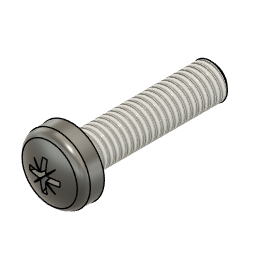
FCW v38 (Autodesk Fusion 360 archive; units mm, degrees)
design "Pan Head Screw SFS-EN ISO 7045 - M3 x 12 - Z Steel 4.6 Plain"
description: Pan Head Screw SFS-EN ISO 7045 - M3 x 12 - Z
part number: SFS-EN ISO 7045 - M3 x 12 - Z Steel 4.6 Plain
Autodesk Fusion 360 part; units mm, degrees
sketch "Sketch1" plane through (0, 0, 0) normal (0, 1, 0) x (1, 0, 0)
  line L0 (-1.5, 1) -> (-1.5, 12)
  line L1 (-1.5, 12) -> (0, 12)
  line L2 (0, 12) -> (0, -2.4)
  line L3 (-1.3647, 0) -> (-2.8, 0)
  arc A0 (-2.7449, -1.5792) -> (0, -2.4) centre (0, 2.6) ccw
  line L4 (-1.5, 1) -> (-1.3647, 0.7098)
  line L5 (-1.3647, 0.7098) -> (-1.3647, 0)
  line L6 (-2.8, 0) -> (-2.7449, -1.5792)
  dimension "d9" = 3
  dimension "d74" = 12
  dimension "d75" = 5.6
  dimension "d78" = 2.4
  dimension "d98" = 2.7294
  dimension "d102" = 1
  dimension "d103" = 155
  dimension "d137" = 2
  dimension "d139" = 5
  constraint vertical L0
  constraint perpendicular L0 L1
  constraint coincident origin L3
  constraint coincident L2 A0.centre
  constraint vertical L2
  constraint vertical L5
  constraint coincident L3.start L5.end
  constraint coincident origin L2
  constraint perpendicular L3 L5
  constraint coincident A0.start L6.end
  measures "d74" distance of origin L1.end
  measures "d78" vertical distance of L2.end L3.end
  measures "d102" distance of L3 L0.start
  measures "d103" angle of L4 L5
  measures "d137" angle of L2 L6
  measures "d139" distance of L2.end A0.centre
revolve "Revolve1" add sketch "Sketch1" angle 360 about axis through (0, 0, -12) along (0, 0, 1) makes body 1
ref_plane "WorkPlane1" through (0, 0, 2.4) normal (0, 0, 1) x (1, 0, 0)
sketch "Sketch7" plane through (0, 0, 2.4) normal (0, 0, 1) x (1, 0, 0)
  line L0 (-0.258, 0.258) -> (0.258, 0.258)
  line L1 (0.258, 0.258) -> (0.258, -0.258)
  line L2 (0.258, -0.258) -> (-0.258, -0.258)
  line L3 (-0.258, -0.258) -> (-0.258, 0.258)
  point P0 (0, 0.258)
  point P1 (-0.258, 0)
  dimension "d65" = 0.516
  dimension "d138" = 0.516
  constraint horizontal L0
  constraint perpendicular L0 L1
  constraint parallel L0 L2
  constraint parallel L1 L3
  constraint midpoint L0 P0
  constraint vertical origin P0
  constraint midpoint L3 P1
  constraint horizontal origin P1
  measures "d65" distance of L0.start L0.end
  measures "d138" distance of L0 L2
extrude "Extrude4" add sketch "Sketch7" against normal blind 1.75 draft -10 separate body makes body 2
sketch "Sketch10" plane through (0, 0, 2.4) normal (0, 0, 1) x (1, 0, 0)
  line L0 (-1.4, 0) -> (1.4, 0) construction
  line L1 (-1.4, 0.215) -> (1.4, 0.215)
  line L2 (1.4, 0.215) -> (1.4, -0.215)
  line L3 (1.4, -0.215) -> (-1.4, -0.215)
  line L4 (-1.4, -0.215) -> (-1.4, 0.215)
  line L5 (-0.215, 1.4) -> (0.215, 1.4)
  line L6 (-0.215, -1.4) -> (-0.215, 1.4)
  line L7 (0.215, 1.4) -> (0.215, -1.4)
  line L8 (0.215, -1.4) -> (-0.215, -1.4)
  dimension "d90" = 2.8
  dimension "d91" = 0.43
  dimension "d119" = 90
  constraint horizontal L0
  constraint midpoint origin L0
  constraint horizontal L1
  constraint vertical L2
  constraint horizontal L3
  constraint vertical L4
  constraint midpoint L0.start L4
  constraint midpoint L0.end L2
  measures "d90" distance of L0.start L0.end
  measures "d91" distance of L1.start L3.end
extrude "Extrude1" add sketch "Sketch10" against normal blind 1.75 draft -6 separate body makes body 3
draft "Draft2" angle -30 neutral plane through (0, 0, 2.4) pull (0, 0, 1) 4 faces at (-0.0104, 1.3387, 1.8167) (1.3387, 0.0104, 1.8167) (-1.3387, -0.0104, 1.8167) (0.0104, -1.3387, 1.8167) on bodies 3
combine "Combine1" operation cut target body 1 tool bodies 2 3
ref_plane "WorkPlane2" through (-0.1972, 1.2767, 2.2302) normal (0, 0, -1) x (-1, 0, 0)
sketch "Sketch8" plane through (-0.2873, 1.3933, 2.2302) normal (0, 0, -1) x (1, 0, 0)
  line L0 (0.2873, 1.3933) -> (1.3763, 2.4823)
  line L1 (2.0373, 1.3933) -> (22.7873, 1.3933)
  point P0 (0.2873, 1.3933)
  dimension "d83" = 1.54
  dimension "d117" = 45
  constraint coincident P0 L0.start
  measures "d83" distance of P0 L0.end
  measures "d117" angle of L0 L1
ref_plane "WorkPlane3" through (0.5445, -0.5445, 2.2302) normal (-0.664463, -0.664463, 0.34202) x (0.707107, -0.707107, 0)
sketch "Sketch9" plane through (0.6151, -0.5905, 2.278) normal (-0.664463, -0.664463, 0.34202) x (0.707107, -0.707107, 0)
  line L0 (-0.8525, -0.0508) -> (0.6875, -0.0508)
  line L1 (0.6875, -0.0508) -> (0.6875, 0.8092)
  line L2 (0.6875, 0.8092) -> (-0.8525, 0.8092)
  line L3 (-0.8525, 0.8092) -> (-0.8525, -0.0508)
  point P0 (-0.8525, -0.0508)
  point P1 (0.6875, -0.0508)
  dimension "d85" = 0.86
  constraint horizontal L0
  constraint vertical L1
  constraint horizontal L2
  constraint vertical L3
  constraint coincident P0 L0.start
  constraint coincident P1 L1
  measures "d85" distance of P1 L1.end
extrude "Extrude6" cut sketch "Sketch9" along normal blind 0.215 draft -50 bodies 1
pattern_circular "C-Pattern1" count 4 over 360 about axis through (0, 0, 1.75) along (0, 0, 1) of "Extrude6"
fillet "Fillet4" radius 0.8 1 edges at (-2.5591, 0.9926, 1.5792) on bodies 1
thread "Thread1" "ISO Metric profile 3.0 M3x0.5 6g" major diameter 2.927 minor diameter 2.3555 pitch 0.5 angle 60 resizes the face on face at (-1.4981, 0.0748, -4.6667) on bodies 1
fillet "Fillet5" radius 0.3 1 edges at (-1.2723, 0.4935, 0) on bodies 1
sketch "Sketch5" plane through (0, 0, 0) normal (0, 1, 0) x (1, 0, 0)
  line L0 (-1.53, 12) -> (-1.53, 11.6933)
  line L1 (-1.53, 11.6933) -> (-1.1933, 12)
  line L2 (0, 12) -> (0, -2.4)
  line L3 (-1.53, 12) -> (0, 12)
  dimension "d114" = 1.53
  dimension "d115" = 0.3067
  dimension "d116" = 1.1933
  constraint coincident L2.start L3.end
  constraint perpendicular L2 L3
  constraint coincident L1.end L3
  constraint perpendicular L0 L3
  measures "d114" distance of origin L0
  measures "d115" vertical distance of L0.end L1.end
  measures "d116" horizontal distance of origin L1.end
revolve "Revolve2" cut sketch "Sketch5" angle 360 about axis through (0, 0, -12) along (0, 0, 1) bodies 1
equation "d9 = adsk_nomdia"
equation "adsk_nomlen = 12.00 mm"
equation "adsk_headh = 2.40 mm"
equation "adsk_headdia = 5.60 mm"
equation "adsk_nomdia = 3.00 mm"
equation "adsk_phildia = 2.80 mm"
equation "d31 = -adsk_phildepth"
equation "adsk_philwidth = 0.43 mm"
equation "adsk_phildepth = 1.75 mm"
equation "d65 = adsk_philwidth * 1.2"
equation "d68 = -adsk_phildepth"
equation "d74 = adsk_nomlen"
equation "d75 = adsk_headdia"
equation "d78 = adsk_headh"
equation "d79 = adsk_headh"
equation "d83 = adsk_phildia / 2 * 1.1"
equation "d85 = adsk_philwidth * 2"
equation "d86 = adsk_philwidth / 2"
equation "d90 = adsk_phildia"
equation "d91 = adsk_philwidth"
equation "adsk_thrlen = 11.00 mm"
equation "d98 = adsk_shnkdia"
equation "adsk_shnkdia = 2.72937 mm"
equation "d102 = adsk_nomlen - adsk_thrlen"
equation "adsk_endpointdia = 2.38655 mm"
equation "adsk_startlen = 0.306725 mm"
equation "d114 = adsk_nomdia * 0.51"
equation "d115 = adsk_startlen"
equation "d116 = adsk_endpointdia / 2"
equation "adsk_ovalrad = 5.00 mm"
equation "adsk_headang = 2.00 deg"
equation "adsk_headtoprad = adsk_headh / 3"
equation "d132 = adsk_midfillet"
equation "adsk_midfillet = adsk_nomdia * 0.1"
equation "d136 = adsk_headtoprad"
equation "d137 = adsk_headang"
equation "d138 = adsk_philwidth * 1.2"
equation "d139 = adsk_ovalrad"

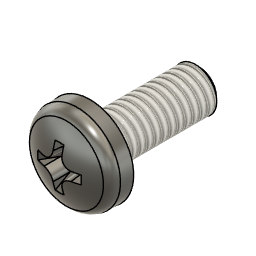
design "Pan Head Screw ISO 7045 - M4 x 10 - H Steel 4.6 Plain"
description: Pan Head Screw ISO 7045 - M4 x 10 - H
part number: ISO 7045 - M4 x 10 - H Steel 4.6 Plain
Autodesk Fusion 360 part; units mm, degrees
sketch "Sketch1" plane through (0, 0, 0) normal (0, 1, 0) x (1, 0, 0)
  line L0 (-2, 1.4) -> (-2, 10)
  line L1 (-2, 10) -> (0, 10)
  line L2 (0, 10) -> (0, -3.1)
  line L3 (-1.8106, 0) -> (-4, 0)
  arc A0 (-3.9381, -1.7712) -> (0, -3.1) centre (0, 3.4) ccw
  line L4 (-2, 1.4) -> (-1.8106, 0.9937)
  line L5 (-1.8106, 0.9937) -> (-1.8106, 0)
  line L6 (-4, 0) -> (-3.9381, -1.7712)
  dimension "d9" = 4
  dimension "d66" = 8
  dimension "d67" = 3.1
  dimension "d68" = 10
  dimension "d75" = 3.6211
  dimension "d77" = 1.4
  dimension "d78" = 155
  dimension "d103" = 2
  dimension "d104" = 6.5
  constraint perpendicular L0 L1
  constraint collinear origin L2.end L1.end
  constraint perpendicular L0 L3
  constraint coincident origin L3
  constraint vertical L0
  constraint vertical L2
  constraint coincident L2 A0.centre
  constraint perpendicular L3 L5
  constraint coincident L3.start L5.end
  measures "d67" vertical distance of L2.end L3.end
  measures "d68" distance of origin L1.end
  measures "d77" distance of L3 L0.start
  measures "d78" angle of L0 L4
  measures "d103" angle of L2 L6
  measures "d104" distance of L2.end A0.centre
revolve "Revolve1" add sketch "Sketch1" angle 360 about axis through (0, 0, -10) along (0, 0, 1) makes body 1
ref_plane "WorkPlane1" through (0, 0, 3.1) normal (0, 0, 1) x (1, 0, 0)
sketch "Sketch2" plane through (0, 0, 3.1) normal (0, 0, 1) x (1, 0, 0)
  line L0 (-0.415, 0.415) -> (-2.2, 0.415)
  line L1 (-0.415, -0.415) -> (-2.2, -0.415)
  line L2 (-2.2, 0.415) -> (-2.2, -0.415)
  line L3 (-0.415, -0.415) -> (-0.415, -2.2)
  line L4 (-0.415, -2.2) -> (0.415, -2.2)
  line L5 (0.415, -0.415) -> (0.415, -2.2)
  line L6 (0.415, -0.415) -> (2.2, -0.415)
  line L7 (2.2, -0.415) -> (2.2, 0.415)
  line L8 (0.415, 0.415) -> (2.2, 0.415)
  line L9 (0.415, 0.415) -> (0.415, 2.2)
  line L10 (0.415, 2.2) -> (-0.415, 2.2)
  line L11 (-0.415, 0.415) -> (-0.415, 2.2)
  point P0 (-2.2, 0)
  dimension "d105" = 0.83
  dimension "d107" = 360
  dimension "d108" = 4.4
  constraint perpendicular L1 L2
  constraint vertical L0.start L1.start
  constraint midpoint L2 P0
  constraint horizontal origin P0
  constraint horizontal L0
  constraint horizontal L1
  constraint coincident L8.start L9.start
  measures "d105" distance of L0 L1
  measures "d108" distance of L2 L7
extrude "Extrude1" add sketch "Sketch2" against normal blind 2.4 draft -4 separate body makes body 2
draft "Draft1" angle -30 neutral plane through (0, 0, 3.1) pull (0, 0, 1) 4 faces at (-2.1441, 0.0824, 2.3) (-0.0824, -2.1441, 2.3) (2.1441, 0.0824, 2.3) (0.0824, 2.1441, 2.3) on bodies 2
fillet "Fillet3" radius 0.83 4 edges at (0.3311, 0.3311, 1.9) (-0.3311, 0.3311, 1.9) (0.3311, -0.3311, 1.9) (-0.3311, -0.3311, 1.9) on bodies 2
combine "Combine1" operation cut target body 1 tool bodies 2
fillet "Fillet4" radius 1.2 1 edges at (-3.6716, 1.4241, 1.7712) on bodies 1
thread "Thread1" "ISO Metric profile 4.0 M4x0.7 6g" major diameter 3.908 minor diameter 3.111 pitch 0.7 angle 60 resizes the face on face at (-1.9975, 0.0997, -4.2667) on bodies 1
fillet "Fillet5" radius 0.4 1 edges at (-1.688, 0.6547, 0) on bodies 1
sketch "Sketch5" plane through (0, 0, 0) normal (0, 1, 0) x (1, 0, 0)
  line L0 (-2.04, 10) -> (-2.04, 9.5706)
  line L1 (-2.04, 9.5706) -> (-1.5706, 10)
  line L2 (0, 10) -> (0, -3.1)
  line L3 (-2.04, 10) -> (0, 10)
  dimension "d89" = 2.04
  dimension "d90" = 0.4294
  dimension "d91" = 1.5706
  constraint coincident L2.start L3.end
  constraint perpendicular L2 L3
  constraint coincident L1.end L3
  constraint perpendicular L0 L3
  measures "d89" distance of origin L0
  measures "d90" vertical distance of L0.end L1.end
  measures "d91" horizontal distance of origin L1.end
revolve "Revolve2" cut sketch "Sketch5" angle 360 about axis through (0, 0, -10) along (0, 0, 1) bodies 1
equation "d9 = adsk_nomdia"
equation "adsk_nomlen = 10.00 mm"
equation "adsk_headh = 3.10 mm"
equation "adsk_headdia = 8.00 mm"
equation "adsk_nomdia = 4.00 mm"
equation "adsk_phildia = 4.40 mm"
equation "d31 = -adsk_phildepth"
equation "adsk_philwidth = 0.83 mm"
equation "adsk_phildepth = 2.40 mm"
equation "d66 = adsk_headdia"
equation "d67 = adsk_headh"
equation "d68 = adsk_nomlen"
equation "d71 = adsk_headh"
equation "adsk_thrlen = 8.60 mm"
equation "d75 = adsk_shnkdia"
equation "adsk_shnkdia = 3.62111 mm"
equation "d77 = adsk_nomlen - adsk_thrlen"
equation "adsk_endpointdia = 3.14117 mm"
equation "adsk_startlen = 0.429415 mm"
equation "d89 = adsk_nomdia * 0.51"
equation "d90 = adsk_startlen"
equation "d91 = adsk_endpointdia / 2"
equation "adsk_ovalrad = 6.50 mm"
equation "adsk_headtoprad = adsk_nomdia * 0.3"
equation "adsk_midfillet = adsk_nomdia * 0.1"
equation "d98 = adsk_midfillet"
equation "adsk_headang = 2.00 deg"
equation "d102 = adsk_headtoprad"
equation "d103 = adsk_headang"
equation "d104 = adsk_ovalrad"
equation "d105 = adsk_philwidth"
equation "d108 = adsk_phildia"
equation "d110 = adsk_philwidth"

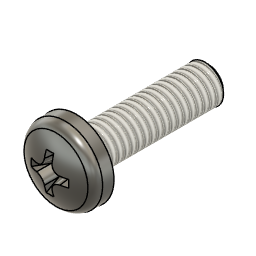
design "Pan Head Screw ISO 7045 - M4 x 14 - H Steel 4.6 Plain"
description: Pan Head Screw ISO 7045 - M4 x 14 - H
part number: ISO 7045 - M4 x 14 - H Steel 4.6 Plain
Autodesk Fusion 360 part; units mm, degrees
sketch "Sketch1" plane through (0, 0, 0) normal (0, 1, 0) x (1, 0, 0)
  line L0 (-2, 1.4) -> (-2, 14)
  line L1 (-2, 14) -> (0, 14)
  line L2 (0, 14) -> (0, -3.1)
  line L3 (-1.8106, 0) -> (-4, 0)
  arc A0 (-3.9381, -1.7712) -> (0, -3.1) centre (0, 3.4) ccw
  line L4 (-2, 1.4) -> (-1.8106, 0.9937)
  line L5 (-1.8106, 0.9937) -> (-1.8106, 0)
  line L6 (-4, 0) -> (-3.9381, -1.7712)
  dimension "d9" = 4
  dimension "d66" = 8
  dimension "d67" = 3.1
  dimension "d68" = 14
  dimension "d75" = 3.6211
  dimension "d77" = 1.4
  dimension "d78" = 155
  dimension "d103" = 2
  dimension "d104" = 6.5
  constraint perpendicular L0 L1
  constraint collinear origin L2.end L1.end
  constraint perpendicular L0 L3
  constraint coincident origin L3
  constraint vertical L0
  constraint vertical L2
  constraint coincident L2 A0.centre
  constraint perpendicular L3 L5
  constraint coincident L3.start L5.end
  measures "d67" vertical distance of L2.end L3.end
  measures "d68" distance of origin L1.end
  measures "d77" distance of L3 L0.start
  measures "d78" angle of L0 L4
  measures "d103" angle of L2 L6
  measures "d104" distance of L2.end A0.centre
revolve "Revolve1" add sketch "Sketch1" angle 360 about axis through (0, 0, -14) along (0, 0, 1) makes body 1
ref_plane "WorkPlane1" through (0, 0, 3.1) normal (0, 0, 1) x (1, 0, 0)
sketch "Sketch2" plane through (0, 0, 3.1) normal (0, 0, 1) x (1, 0, 0)
  line L0 (-0.415, 0.415) -> (-2.2, 0.415)
  line L1 (-0.415, -0.415) -> (-2.2, -0.415)
  line L2 (-2.2, 0.415) -> (-2.2, -0.415)
  line L3 (-0.415, -0.415) -> (-0.415, -2.2)
  line L4 (-0.415, -2.2) -> (0.415, -2.2)
  line L5 (0.415, -0.415) -> (0.415, -2.2)
  line L6 (0.415, -0.415) -> (2.2, -0.415)
  line L7 (2.2, -0.415) -> (2.2, 0.415)
  line L8 (0.415, 0.415) -> (2.2, 0.415)
  line L9 (0.415, 0.415) -> (0.415, 2.2)
  line L10 (0.415, 2.2) -> (-0.415, 2.2)
  line L11 (-0.415, 0.415) -> (-0.415, 2.2)
  point P0 (-2.2, 0)
  dimension "d105" = 0.83
  dimension "d107" = 360
  dimension "d108" = 4.4
  constraint perpendicular L1 L2
  constraint vertical L0.start L1.start
  constraint midpoint L2 P0
  constraint horizontal origin P0
  constraint horizontal L0
  constraint horizontal L1
  constraint coincident L8.start L9.start
  measures "d105" distance of L0 L1
  measures "d108" distance of L2 L7
extrude "Extrude1" add sketch "Sketch2" against normal blind 2.4 draft -4 separate body makes body 2
draft "Draft1" angle -30 neutral plane through (0, 0, 3.1) pull (0, 0, 1) 4 faces at (-2.1441, 0.0824, 2.3) (-0.0824, -2.1441, 2.3) (2.1441, 0.0824, 2.3) (-0.0824, 2.1441, 2.3) on bodies 2
fillet "Fillet3" radius 0.83 4 edges at (0.3311, 0.3311, 1.9) (-0.3311, 0.3311, 1.9) (0.3311, -0.3311, 1.9) (-0.3311, -0.3311, 1.9) on bodies 2
combine "Combine1" operation cut target body 1 tool bodies 2
fillet "Fillet4" radius 1.2 1 edges at (-3.6716, 1.4241, 1.7712) on bodies 1
thread "Thread1" "ISO Metric profile 4.0 M4x0.7 6g" major diameter 3.908 minor diameter 3.111 pitch 0.7 angle 60 resizes the face on face at (-1.9975, 0.0997, -5.6) on bodies 1
fillet "Fillet5" radius 0.4 1 edges at (-1.688, 0.6547, 0) on bodies 1
sketch "Sketch5" plane through (0, 0, 0) normal (0, 1, 0) x (1, 0, 0)
  line L0 (-2.04, 14) -> (-2.04, 13.5706)
  line L1 (-2.04, 13.5706) -> (-1.5706, 14)
  line L2 (0, 14) -> (0, -3.1)
  line L3 (-2.04, 14) -> (0, 14)
  dimension "d89" = 2.04
  dimension "d90" = 0.4294
  dimension "d91" = 1.5706
  constraint coincident L2.start L3.end
  constraint perpendicular L2 L3
  constraint coincident L1.end L3
  constraint perpendicular L0 L3
  measures "d89" distance of origin L0
  measures "d90" vertical distance of L0.end L1.end
  measures "d91" horizontal distance of origin L1.end
revolve "Revolve2" cut sketch "Sketch5" angle 360 about axis through (0, 0, -14) along (0, 0, 1) bodies 1
equation "d9 = adsk_nomdia"
equation "adsk_nomlen = 14.00 mm"
equation "adsk_headh = 3.10 mm"
equation "adsk_headdia = 8.00 mm"
equation "adsk_nomdia = 4.00 mm"
equation "adsk_phildia = 4.40 mm"
equation "d31 = -adsk_phildepth"
equation "adsk_philwidth = 0.83 mm"
equation "adsk_phildepth = 2.40 mm"
equation "d66 = adsk_headdia"
equation "d67 = adsk_headh"
equation "d68 = adsk_nomlen"
equation "d71 = adsk_headh"
equation "adsk_thrlen = 12.60 mm"
equation "d75 = adsk_shnkdia"
equation "adsk_shnkdia = 3.62111 mm"
equation "d77 = adsk_nomlen - adsk_thrlen"
equation "adsk_endpointdia = 3.14117 mm"
equation "adsk_startlen = 0.429415 mm"
equation "d89 = adsk_nomdia * 0.51"
equation "d90 = adsk_startlen"
equation "d91 = adsk_endpointdia / 2"
equation "adsk_ovalrad = 6.50 mm"
equation "adsk_headtoprad = adsk_nomdia * 0.3"
equation "adsk_midfillet = adsk_nomdia * 0.1"
equation "d98 = adsk_midfillet"
equation "adsk_headang = 2.00 deg"
equation "d102 = adsk_headtoprad"
equation "d103 = adsk_headang"
equation "d104 = adsk_ovalrad"
equation "d105 = adsk_philwidth"
equation "d108 = adsk_phildia"
equation "d110 = adsk_philwidth"

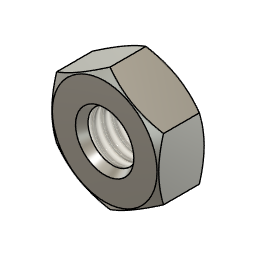
design "Hexagon Regular Nut ISO 4032 - M3 Steel 6 Plain"
description: Hexagon Regular Nut ISO 4032 - M3
part number: ISO 4032 - M3 Steel 6 Plain
Autodesk Fusion 360 part; units mm, degrees
sketch "Sketch1" plane through (0, 0, 0) normal (0, 1, 0) x (1, 0, 0)
  line L0 (0, 0) -> (0, -2.4)
  line L1 (-1.5, 0) -> (-2.695, 0)
  line L2 (-2.695, 0) -> (-3.1763, -0.2778)
  line L3 (-3.1763, -0.2778) -> (-3.1763, -2.1222)
  line L4 (-3.1763, -2.1222) -> (-2.695, -2.4)
  line L5 (-2.695, -2.4) -> (-1.5, -2.4)
  line L6 (-1.5, -2.4) -> (-1.5, 0)
  dimension "d121" = 3
  dimension "d122" = 30
  dimension "d123" = 30
  dimension "d126" = 2.4
  dimension "d128" = 6.3525
  dimension "d172" = 5.39
  constraint vertical L0
  constraint coincident L0 L0.end
  constraint coincident origin L0
  constraint horizontal L1
  constraint perpendicular L1 L3
  constraint perpendicular L3 L5
  constraint perpendicular L5 L6
  constraint coincident L0.start L1
  constraint coincident L0.start origin
  constraint coincident L0.end L5
  constraint vertical L1.end L4.end
  measures "d122" angle of L1 L2
  measures "d123" angle of L4 L5
  measures "d126" distance of L1.start L5.end
revolve "Revolve1" add sketch "Sketch1" angle 360 about axis through (0, 0, 0) along (0, 0, 1)
sketch "Sketch8" plane through (0, 0, 2.4) normal (0, 0, 1) x (1, 0, 0)
  line L0 (0, 0) -> (-5.5, 0) construction
  line L1 (-2.75, -1.5894) -> (-2.75, 1.5894)
  circle A0 centre (0, 0) radius 1.5
  circle A1 centre (0, 0) radius 3.1763
  dimension "d114" = 2.75
  constraint horizontal L0
  constraint perpendicular L0 L1
  constraint midpoint L0 L1
  constraint coincident L0.start A0.centre
  constraint coincident L1.end A1
  measures "d114" distance of L0.start L1
extrude "Extrude5" cut sketch "Sketch8" against normal blind 2.4 contours L1 A1 picked at (-2.8188, 0.3871)
pattern_circular "C-Pattern2" count 6 over 360 about axis through (0, 0, 1.75) along (0, 0, 1) of "Extrude5"
thread "Thread3" "ISO Metric profile 3.0 M3x0.5 6H" major diameter 3.086 minor diameter 2.529 pitch 0.5 angle 60 resizes the face on face at (-1.4925, 0.1494, 1.6)
sketch "Sketch12" plane through (0, 0, 0) normal (0, 1, 0) x (1, 0, 0)
  line L0 (1.2645, -2.4) -> (-1.2645, -2.4)
  line L1 (2.695, -2.4) -> (-2.695, -2.4)
  line L2 (2.695, 0) -> (-2.695, 0)
  line L3 (1.2645, 0) -> (-1.2645, 0)
  line L4 (-1.5, 0) -> (0, 0)
  line L5 (-0.8072, -1.2) -> (-1.5, 0)
  line L6 (-1.5, -2.4) -> (0, -2.4)
  line L7 (-0.8072, -1.2) -> (-1.5, -2.4)
  line L8 (0, 0) -> (0, -2.4)
  dimension "d165" = 60
  dimension "d169" = 60
  dimension "d170" = 1.5
  constraint horizontal L4
  constraint collinear L1 L6
  constraint coincident L5.start L7.start
  constraint vertical L4.start L6.start
  constraint coincident L1 L6.end
  constraint coincident L6.end L8.end
  constraint coincident L4.end L8.start
  measures "d165" angle of L2 L5
  measures "d169" angle of L6 L7
  measures "d170" distance of L4.start L4.end
revolve "Revolve3" cut sketch "Sketch12" angle 360 about axis through (0, 0, 1.75) along (0, 0, 1)
equation "adsk_nheig = 2.40 mm"
equation "adsk_maxdia = 6.3525 mm"
equation "adsk_nomdia = 3.00 mm"
equation "d89 = -adsk_nheig"
equation "adsk_waflat = 5.50 mm"
equation "d114 = adsk_waflat / 2"
equation "adsk_chamang1 = 30.00 deg"
equation "adsk_chamang2 = 30.00 deg"
equation "d121 = adsk_nomdia"
equation "d122 = adsk_chamang1"
equation "d123 = adsk_chamang2"
equation "d126 = adsk_nheig"
equation "d128 = adsk_maxdia"
equation "d163 = adsk_nheig"
equation "d170 = adsk_nomdia * 0.5"
equation "adsk_beardia = 5.39 mm"
equation "d172 = adsk_beardia"
